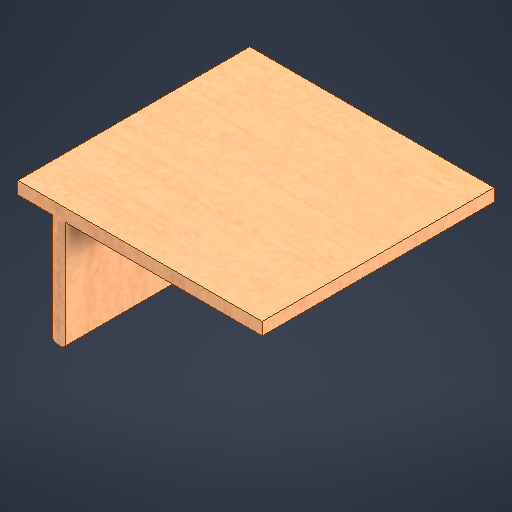
# Autodesk Inventor part: caddy top
Saved by Autodesk Inventor 2027.1 (Build 311270010, 270A)
## iProperties
Created: 2026-10-22
Part Number: caddy top
Material: Wood (Cherry)
Document SubType Name: Modeling
Designer: wh29971
Density: 0.63 g/cm^3
Appearance: Cherry - Natural Low Gloss
Author: wh29971
Autodesk Inventor part; units mm, degrees
ref_plane "YZ Plane" through (0, 0, 0) normal (1, 0, 0) x (0, 1, 0)
ref_plane "XZ Plane" through (0, 0, 0) normal (0, 1, 0) x (-1, 0, 0)
ref_plane "XY Plane" through (0, 0, 0) normal (0, 0, 1) x (1, 0, 0)
sketch "Sketch1" plane through (0, 0, 0) normal (0, 1, 0) x (-1, 0, 0)
  line L0 (-50, -47.5) -> (50, -47.5)
  line L1 (50, -47.5) -> (50, 47.5)
  line L2 (50, 47.5) -> (-50, 47.5)
  line L3 (-50, 47.5) -> (-50, -47.5)
  line L4 (-50, -47.5) -> (50, 47.5) construction
  line L5 (50, -47.5) -> (-50, 47.5) construction
  line L6 (35, 47.5) -> (35, -47.5)
  line L7 (27.5, -47.5) -> (27.5, 47.5)
  point P0 (0, 0)
  dimension "d0" = 100
  dimension "d1" = 95
  dimension "d2" = 7.5
  dimension "d3" = 15
  constraints: 16 end point, 4 point on line, 3 perpendicular, 2 midpoint, 2 parallel, 1 horizontal
  measures "d0" distance of L1.end L2.end
  measures "d1" distance of L0.end L1.end
  measures "d2" distance between parallel lines of L6 L7
  measures "d3" distance between parallel lines of L1 L6
extrude "Extrusion1" add sketch "Sketch1" along normal blind 5
sketch "Sketch3" plane through (0, 0, 0) normal (0, -1, 0) x (1, 0, 0)
  circle A0 centre (10, 0) radius 25
  line L0 (6, 26.7814) -> (14, 26.7814) construction
  line L1 (14, 26.7814) -> (12.5, 30.7814)
  line L2 (12.5, 30.7814) -> (7.5, 30.7814)
  line L3 (7.5, 30.7814) -> (6, 26.7814)
  line L4 (-5.2239, 22.3937) -> (1.9839, 25.8647) construction
  line L5 (-5.608, 26.6484) -> (-5.2239, 22.3937)
  line L6 (-1.1031, 28.8178) -> (-5.608, 26.6484)
  line L7 (1.9839, 25.8647) -> (-1.1031, 28.8178)
  line L8 (-13.4325, 13.5706) -> (-8.4446, 19.8252) construction
  line L9 (-15.6246, 17.2373) -> (-13.4325, 13.5706)
  line L10 (-12.5071, 21.1465) -> (-15.6246, 17.2373)
  line L11 (-8.4446, 19.8252) -> (-12.5071, 21.1465)
  line L12 (-17, 2.0597) -> (-15.2198, 9.8591) construction
  line L13 (-20.5659, 4.4122) -> (-17, 2.0597)
  line L14 (-19.4533, 9.2868) -> (-20.5659, 4.4122)
  line L15 (-15.2198, 9.8591) -> (-19.4533, 9.2868)
  line L16 (-15.2198, -9.8591) -> (-17, -2.0597) construction
  line L17 (-19.4533, -9.2868) -> (-15.2198, -9.8591)
  line L18 (-20.5659, -4.4122) -> (-19.4533, -9.2868)
  line L19 (-17, -2.0597) -> (-20.5659, -4.4122)
  line L20 (-8.4446, -19.8252) -> (-13.4325, -13.5706) construction
  line L21 (-12.5071, -21.1465) -> (-8.4446, -19.8252)
  line L22 (-15.6246, -17.2373) -> (-12.5071, -21.1465)
  line L23 (-13.4325, -13.5706) -> (-15.6246, -17.2373)
  line L24 (1.9839, -25.8647) -> (-5.2239, -22.3937) construction
  line L25 (-1.1031, -28.8178) -> (1.9839, -25.8647)
  line L26 (-5.608, -26.6484) -> (-1.1031, -28.8178)
  line L27 (-5.2239, -22.3937) -> (-5.608, -26.6484)
  line L28 (14, -26.7814) -> (6, -26.7814) construction
  line L29 (12.5, -30.7814) -> (14, -26.7814)
  line L30 (7.5, -30.7814) -> (12.5, -30.7814)
  line L31 (6, -26.7814) -> (7.5, -30.7814)
  line L32 (25.2239, -22.3937) -> (18.0161, -25.8647) construction
  line L33 (25.608, -26.6484) -> (25.2239, -22.3937)
  line L34 (21.1031, -28.8178) -> (25.608, -26.6484)
  line L35 (18.0161, -25.8647) -> (21.1031, -28.8178)
  line L36 (33.4325, -13.5706) -> (28.4446, -19.8252) construction
  line L37 (35.6246, -17.2373) -> (33.4325, -13.5706)
  line L38 (32.5071, -21.1465) -> (35.6246, -17.2373)
  line L39 (28.4446, -19.8252) -> (32.5071, -21.1465)
  line L40 (37, -2.0597) -> (35.2198, -9.8591) construction
  line L41 (40.5659, -4.4122) -> (37, -2.0597)
  line L42 (39.4533, -9.2868) -> (40.5659, -4.4122)
  line L43 (35.2198, -9.8591) -> (39.4533, -9.2868)
  line L44 (35.2198, 9.8591) -> (37, 2.0597) construction
  line L45 (39.4533, 9.2868) -> (35.2198, 9.8591)
  line L46 (40.5659, 4.4122) -> (39.4533, 9.2868)
  line L47 (37, 2.0597) -> (40.5659, 4.4122)
  line L48 (28.4446, 19.8252) -> (33.4325, 13.5706) construction
  line L49 (32.5071, 21.1465) -> (28.4446, 19.8252)
  line L50 (35.6246, 17.2373) -> (32.5071, 21.1465)
  line L51 (33.4325, 13.5706) -> (35.6246, 17.2373)
  line L52 (18.0161, 25.8647) -> (25.2239, 22.3937) construction
  line L53 (21.1031, 28.8178) -> (18.0161, 25.8647)
  line L54 (25.608, 26.6484) -> (21.1031, 28.8178)
  line L55 (25.2239, 22.3937) -> (25.608, 26.6484)
  line L56 (-17, 2.0597) -> (-17, -2.0597)
  line L57 (-8.4446, 19.8252) -> (-5.2239, 22.3937)
  line L58 (1.9839, 25.8647) -> (6, 26.7814)
  line L59 (14, 26.7814) -> (18.0161, 25.8647)
  line L60 (25.2239, 22.3937) -> (28.4446, 19.8252)
  line L61 (33.4325, 13.5706) -> (35.2198, 9.8591)
  line L62 (37, 2.0597) -> (37, -2.0597)
  line L63 (-13.4325, 13.5706) -> (-15.2198, 9.8591)
  line L64 (-15.2198, -9.8591) -> (-13.4325, -13.5706)
  line L65 (-8.4446, -19.8252) -> (-5.2239, -22.3937)
  line L66 (1.9839, -25.8647) -> (6, -26.7814)
  line L67 (14, -26.7814) -> (18.0161, -25.8647)
  line L68 (25.2239, -22.3937) -> (28.4446, -19.8252)
  line L69 (33.4325, -13.5706) -> (35.2198, -9.8591)
  line L70 (-50, 47.5) -> (50, 47.5) construction
  line L71 (50, -47.5) -> (-50, -47.5) construction
  line L72 (-50, -47.5) -> (-50, 47.5) projected
  line L73 (-50, 0) -> (50, 0) construction
  line L74 (50, 47.5) -> (50, -47.5) projected
  point P0 (0, 0)
  point P1 (10, 26.7814)
  point P2 (-1.62, 24.1292)
  point P3 (-10.9385, 16.6979)
  point P4 (-16.1099, 5.9594)
  point P5 (-16.1099, -5.9594)
  point P6 (-10.9385, -16.6979)
  point P7 (-1.62, -24.1292)
  point P8 (10, -26.7814)
  point P9 (21.62, -24.1292)
  point P10 (30.9385, -16.6979)
  point P11 (36.1099, -5.9594)
  point P12 (36.1099, 5.9594)
  point P13 (30.9385, 16.6979)
  point P14 (21.62, 24.1292)
  dimension "d26" = 50
  dimension "d27" = 4
  dimension "d28" = 5
  dimension "d29" = 8
  dimension "d31" = 360
  dimension "d35" = 40
  dimension "d36" = 3.5659
  dimension "d37" = 27
  constraints: 142 end point, 3 midpoint, 1 centre point, 1 equal length, 1 horizontal, 1 point on line, 1 vertical, 127 other
  measures "d26" diameter of A0
  measures "d27" vertical distance of L2.end L0.start
  measures "d28" distance of L1.end L2.end
  measures "d29" distance of L0.start L0.end
  measures "d35" distance from line of L74 A0.centre
  measures "d36" horizontal distance of L14.end L12.start
  measures "d37" distance from line of A0.centre L69
emboss "Emboss2" sketch "Sketch3" operation cut depth 1 direction (0, 1, 0)
sketch "Sketch4" plane through (0, 0, 0) normal (0, -1, 0) x (1, 0, 0)
  line L0 (50, -47.5) -> (-50, -47.5) projected
  line L1 (-30, -47.5) -> (-30, 47.5)
  line L2 (-50, 47.5) -> (50, 47.5) projected
  line L3 (-35, 47.5) -> (-35, -47.5)
  line L4 (-50, -47.5) -> (-50, 47.5) projected
  line L5 (-35, -47.5) -> (-30, -47.5)
  line L6 (-35, 47.5) -> (-30, 47.5)
  point P0 (0, 0)
  dimension "d38" = 5
  dimension "d39" = 15
  constraints: 8 end point, 4 point on line, 1 collinear, 1 horizontal, 1 perpendicular, 1 vertical
  measures "d38" distance between parallel lines of L1 L3
  measures "d39" distance between parallel lines of L4 L3
extrude "Extrusion3" add sketch "Sketch4" along normal blind 45 contours L0 L3 L2 L1
chamfer "Chamfer1" distance 2 angle 45 4 edges at (-30, -45, 0) (-35, -45, 0) (-32.5, -45, -47.5) (-32.5, -45, 47.5)
thicken "Thicken1" operation cut thickness 1 both sides no extend neighbours yes toward (0, 0, -1) faces at (-10, 3.3333, 47.5) (50, 1.6667, 15.8333) (-10, 3.3333, -47.5) (-50, 3.3333, -15.8333)
body "Solid1"
